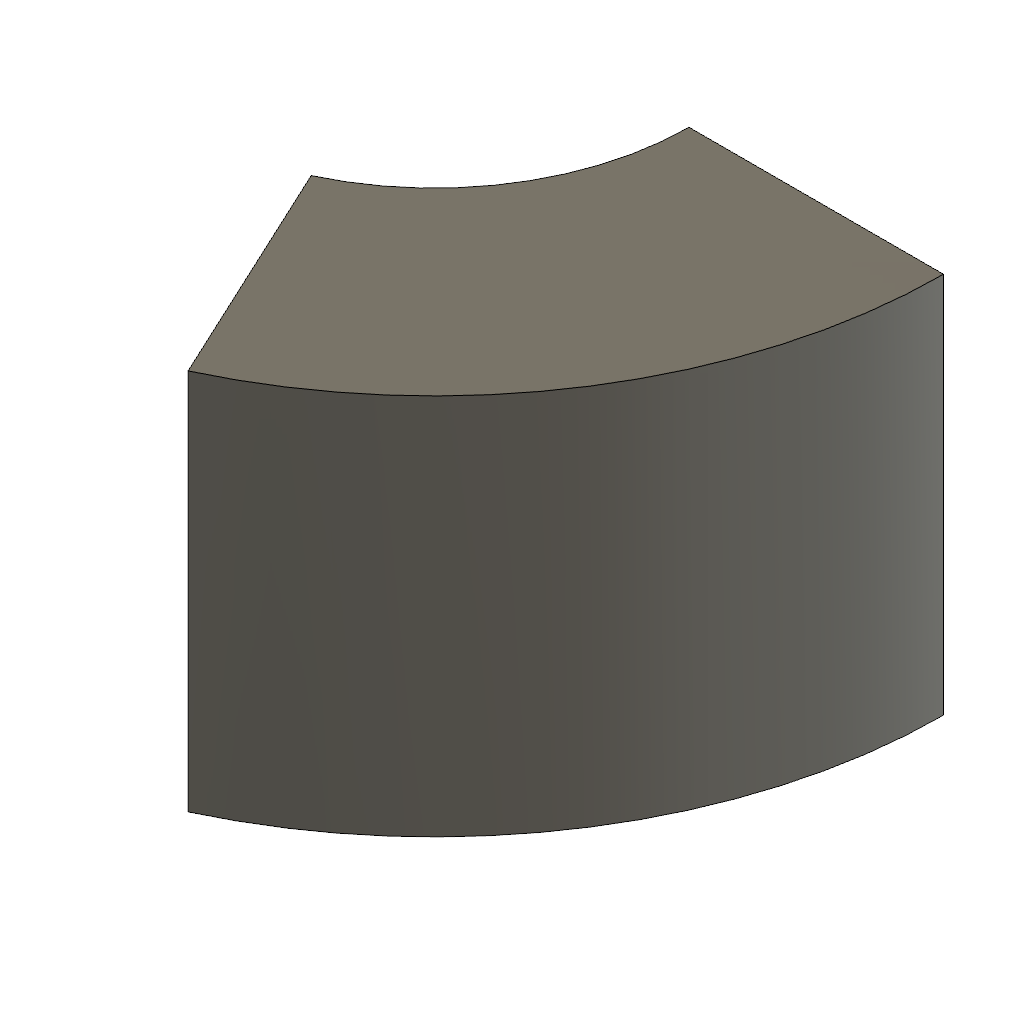
revolve_partial (Autodesk Fusion 360 design; units mm, degrees)
part number: 2026-10-20-17-27-57-489
Autodesk Fusion 360 part; units mm, degrees
sketch "RevolveProfile" plane through (0, 0, 0) normal (0, 0, 1) x (1, 0, 0)
  line L0 (10, 0) -> (20, 0)
  line L1 (20, 0) -> (20, 15)
  line L2 (20, 15) -> (10, 15)
  line L3 (10, 15) -> (10, 0)
revolve "ProbeRevolve" add sketch "RevolveProfile" angle 65 about axis through (0, 1.75, 0) along (0, -1, 0)
